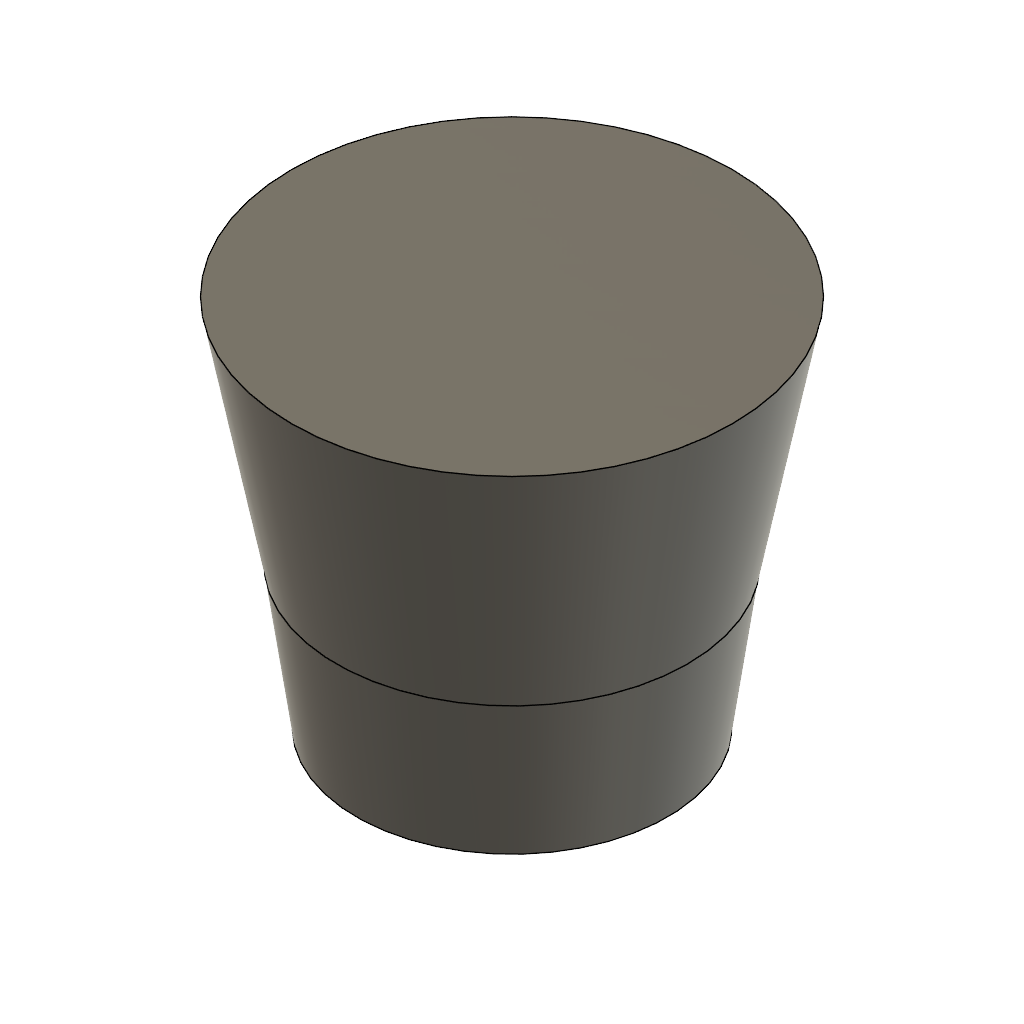
holdout_a (Autodesk Fusion 360 design; units mm, degrees)
part number: 2026-11-27-16-39-53-047
Autodesk Fusion 360 part; units mm, degrees
sketch "CircularProfile" plane through (0, 0, 0) normal (0, 1, 0) x (1, 0, 0)
  circle A0 centre (19, 5) radius 16
extrude "TwoSidedDraft" add sketch "CircularProfile" along normal blind 21 draft 11 and the other way blind 13 draft -8
